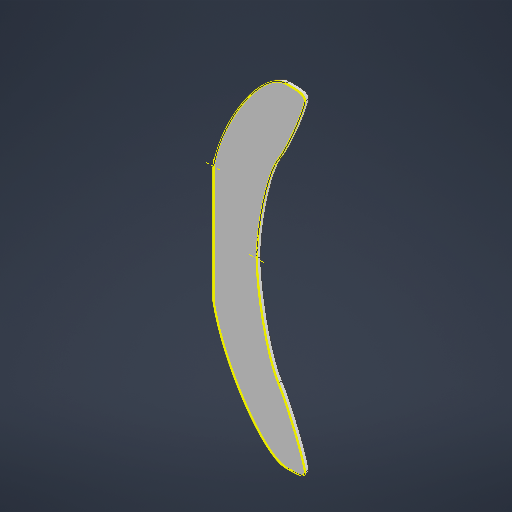
# Autodesk Inventor part: vây đuôi phương án C
Saved by Autodesk Inventor 2027 (Build 310192060, 192F)
## iProperties
Created: 2026-08-20
Part Number: vây đuôi phương án C
Material: Generic
Document SubType Name: Modeling
Designer: Laptop
Density: 1 g/cm^3
Appearance: Default
Author: Laptop
Autodesk Inventor part; units mm, degrees
ref_plane "YZ Plane" through (0, 0, 0) normal (1, 0, 0) x (0, 1, 0)
ref_plane "XZ Plane" through (0, 0, 0) normal (0, 1, 0) x (-1, 0, 0)
ref_plane "XY Plane" through (0, 0, 0) normal (0, 0, 1) x (1, 0, 0)
sketch "Sketch1" plane through (0, 0, 0) normal (0, 0, 1) x (1, 0, 0)
  line L0 (0, 0) -> (0, 21) construction
  line L1 (0, 21) -> (3.474, 39) construction
  line L2 (3.474, 39) -> (18.237, 60) construction
  line L3 (18.237, 60) -> (26.053, 60) construction
  line L4 (26.053, 60) -> (30.395, 60) construction
  line L5 (30.395, 60) -> (33, 60) construction
  line L6 (33, 60) -> (33, 58) construction
  line L7 (33, 58) -> (33, 56) construction
  line L8 (33, 56) -> (27.789, 42) construction
  line L9 (27.789, 42) -> (23.447, 35) construction
  line L10 (23.447, 35) -> (19.105, 28) construction
  line L11 (19.105, 28) -> (15.632, 10) construction
  line L12 (15.632, 10) -> (15.632, 0) construction
  line L13 (0, 21) -> (3.474, 39) construction
  line L14 (3.474, 39) -> (18.237, 60) construction
  line L15 (18.237, 60) -> (26.053, 60) construction
  spline S0 degree 3 poles (0, 21) (3.474, 39) (18.237, 60) (26.053, 60) knots 1 1 1 1 2 2 2 2
  line L16 (26.053, 60) -> (30.395, 60) construction
  line L17 (30.395, 60) -> (33, 60) construction
  line L18 (33, 60) -> (33, 58) construction
  spline S1 degree 3 poles (26.053, 60) (30.395, 60) (33, 60) (33, 58) knots 1 1 1 1 2 2 2 2
  line L19 (33, 58) -> (33, 56) construction
  line L20 (33, 56) -> (27.789, 42) construction
  line L21 (27.789, 42) -> (23.447, 35) construction
  spline S2 degree 3 poles (33, 58) (33, 56) (27.789, 42) (23.447, 35) knots 1 1 1 1 2 2 2 2
  line L22 (23.447, 35) -> (19.105, 28) construction
  line L23 (19.105, 28) -> (15.632, 10) construction
  line L24 (15.632, 10) -> (15.632, 0) construction
  spline S3 degree 3 poles (23.447, 35) (19.105, 28) (15.632, 10) (15.632, 0) knots 1 1 1 1 2 2 2 2
  line L25 (0, 21) -> (0, 0)
  line L26 (0, 0) -> (0, -21) construction
  line L27 (0, -21) -> (3.474, -39) construction
  line L28 (3.474, -39) -> (18.237, -60) construction
  line L29 (18.237, -60) -> (26.053, -60) construction
  line L30 (26.053, -60) -> (30.395, -60) construction
  line L31 (30.395, -60) -> (33, -60) construction
  line L32 (33, -60) -> (33, -58) construction
  line L33 (33, -58) -> (33, -56) construction
  line L34 (33, -56) -> (27.789, -42) construction
  line L35 (27.789, -42) -> (23.447, -35) construction
  line L36 (23.447, -35) -> (19.105, -28) construction
  line L37 (19.105, -28) -> (15.632, -10) construction
  line L38 (15.632, -10) -> (15.632, 0) construction
  line L39 (0, -21) -> (3.474, -39) construction
  line L40 (3.474, -39) -> (18.237, -60) construction
  line L41 (18.237, -60) -> (26.053, -60) construction
  spline S4 degree 3 poles (0, -21) (3.474, -39) (18.237, -60) (26.053, -60) knots 1 1 1 1 2 2 2 2
  line L42 (26.053, -60) -> (30.395, -60) construction
  line L43 (30.395, -60) -> (33, -60) construction
  line L44 (33, -60) -> (33, -58) construction
  spline S5 degree 3 poles (26.053, -60) (30.395, -60) (33, -60) (33, -58) knots 1 1 1 1 2 2 2 2
  line L45 (33, -58) -> (33, -56) construction
  line L46 (33, -56) -> (27.789, -42) construction
  line L47 (27.789, -42) -> (23.447, -35) construction
  spline S6 degree 3 poles (33, -58) (33, -56) (27.789, -42) (23.447, -35) knots 1 1 1 1 2 2 2 2
  line L48 (23.447, -35) -> (19.105, -28) construction
  line L49 (19.105, -28) -> (15.632, -10) construction
  line L50 (15.632, -10) -> (15.632, 0) construction
  spline S7 degree 3 poles (23.447, -35) (19.105, -28) (15.632, -10) (15.632, 0) knots 1 1 1 1 2 2 2 2
  line L51 (0, -21) -> (0, 0)
  constraints: 56 end point, 17 collinear, 16 coincident, 2 perpendicular, 1 parallel, 1 vertical, 24 other
extrude "Extrusion1" add sketch "Sketch1" along normal mid plane 1.4
sketch "Sketch2" plane through (0, 0, 0.7) normal (0, 0, 1) x (1, 0, 0)
  line L0 (0, 21) -> (0, -21) projected
  line L1 (0, -21) -> (0, 21) projected
  line L2 (0, 21) -> (0, -21) projected
  line L3 (0, -21) -> (0, 21) projected
  line L4 (0, 21) -> (0, -21) projected
  line L5 (0, -21) -> (0, 21) projected
  point P0 (15.632, 0)
  point P1 (23.447, 35)
  point P2 (26.053, 60)
  point P3 (26.053, 60)
  point P4 (26.053, 60)
  point P5 (33, 58)
  point P6 (33, 58)
  point P7 (33, 58)
  point P8 (23.447, 35)
  point P9 (23.447, 35)
  point P10 (26.053, 60)
  point P11 (26.053, 60)
  point P12 (33, 58)
  point P13 (33, 58)
  point P14 (23.447, 35)
  point P15 (23.447, 35)
  point P16 (15.632, 0)
  point P17 (15.632, 0)
  point P18 (26.053, -60)
  point P19 (33, -58)
  point P20 (23.447, -35)
  point P21 (26.053, -60)
  point P22 (33, -58)
  point P23 (23.447, -35)
  point P24 (15.632, 0)
  point P25 (23.447, 35)
  point P26 (33, 58)
  point P27 (26.053, 60)
  point P28 (33, -58)
  point P29 (26.053, -60)
  point P30 (26.053, 60)
  point P31 (33, 58)
  point P32 (23.447, 35)
  point P33 (15.632, 0)
  point P34 (23.447, -35)
  point P35 (15.632, 0)
  point P36 (15.632, 0)
  point P37 (23.447, -35)
  point P38 (23.447, -35)
  point P39 (23.447, -35)
  point P40 (23.447, -35)
  point P41 (33, -58)
  point P42 (33, -58)
  point P43 (33, -58)
  point P44 (33, -58)
  point P45 (26.053, -60)
  point P46 (26.053, -60)
  point P47 (26.053, -60)
  point P48 (26.053, -60)
  constraints: 48 other
body "Solid1"
